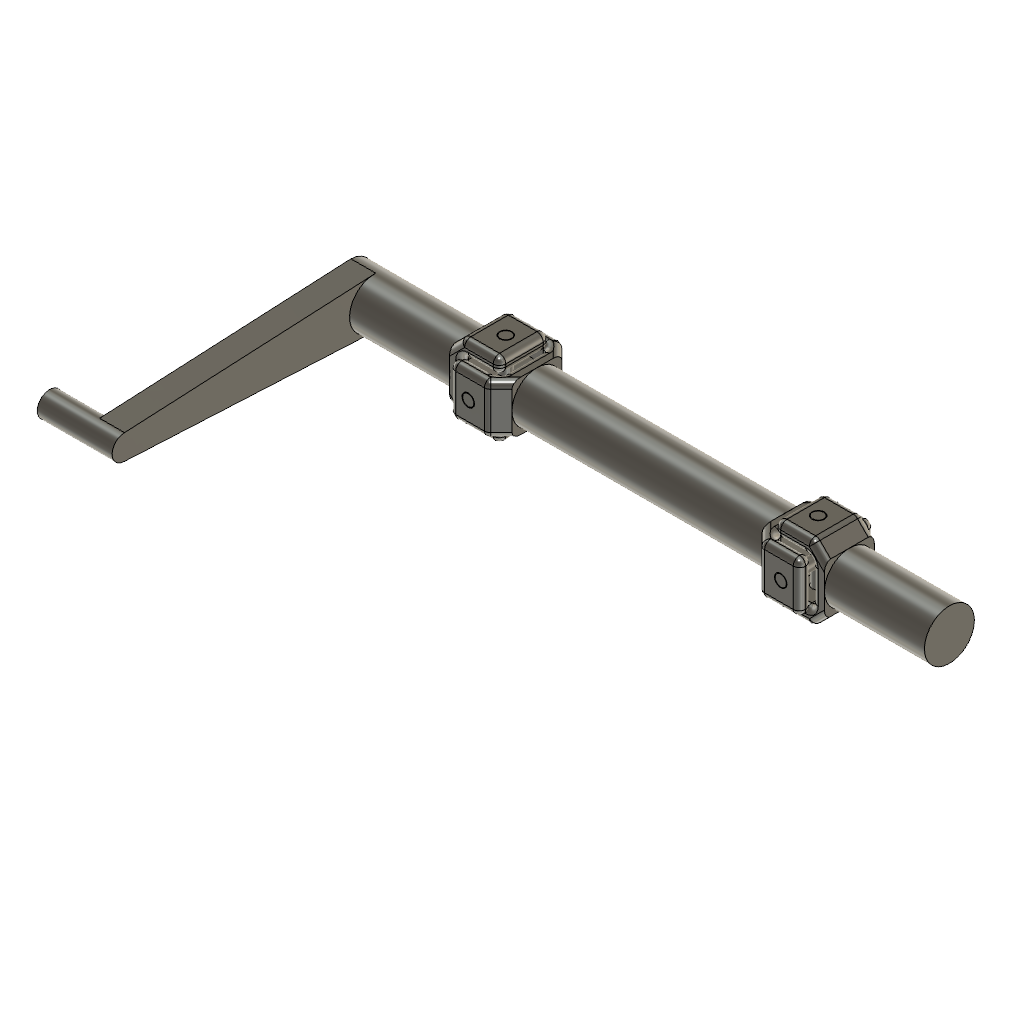
Constant Velocity joint (Autodesk Fusion 360 design; units mm, degrees)
Autodesk Fusion 360 part; units mm, degrees
sketch "Sketch1" plane through (0, 0, 0) normal (1, 0, 0) x (0, 1, 0)
  circle A0 centre (0, 0) radius 1
  dimension "d1" = 2
  constraint coincident A0.centre origin
  measures "d1" diameter of A0
extrude "Extrude1" add sketch "Sketch1" along normal blind 4 makes body 1 in component "Component"
sketch "Sketch2" plane through (0, 0, 0) normal (0, 1, 0) x (1, 0, 0)
  line L0 (4, -1) -> (4.5, -1.5)
  line L1 (4.5, -1.5) -> (6, -1.5)
  line L2 (6, -1.5) -> (6, -0.9)
  line L3 (6, -0.9) -> (4.5, -0.9)
  line L4 (4.5, -0.9) -> (4.5, 0.9)
  line L5 (4.5, 0.9) -> (6, 0.9)
  line L6 (6, 0.9) -> (6, 1.5)
  line L7 (6, 1.5) -> (4.5, 1.5)
  line L8 (4.5, 1.5) -> (4, 1)
  line L9 (4, 1) -> (4, -1)
  constraint horizontal L1
  constraint perpendicular L1 L2
  constraint perpendicular L2 L3
  constraint perpendicular L3 L4
  constraint perpendicular L4 L5
  constraint perpendicular L5 L6
  constraint perpendicular L6 L7
  constraint perpendicular L7 L9
extrude "Extrude2" add sketch "Sketch2" along normal mid plane 2 bodies 1 in component "Component"
fillet "Fillet1" radius 0.25 6 edges at (6, 0, 1.5) (6, 0, 0.9) (4.5, 0, 0.9) (4.5, 0, -0.9) (6, 0, -0.9) (6, 0, -1.5) on bodies 1 in component "Component"
fillet "Fillet1" radius 0.25 2 edges at (4.5, 0, 1.5) (4.5, 0, -1.5) on bodies 1 in component "Component"
sketch "Sketch3" plane through (0, 0, 1.5) normal (0, 0, 1) x (-1, 0, 0)
  line L0 (-4.6036, -1) -> (-4.6036, 1)
  line L1 (-4.6036, 1) -> (-5.75, 1)
  line L2 (-5.75, 1) -> (-5.75, -1)
  line L3 (-5.75, -1) -> (-4.6036, -1)
  circle A0 centre (-5.25, 0) radius 0.25
  dimension "d10" = 0.5
  measures "d10" diameter of A0
extrude "Extrude3" cut sketch "Sketch3" against normal blind 3 contours A0 bodies 1 in component "Component"
sketch "Sketch4" plane through (0, 0, 1.5) normal (0, 0, 1) x (-1, 0, 0)
  circle A0 centre (-5.25, 0) radius 0.25
  line L0 (-4.6036, -1) -> (-4.6036, 1)
  line L1 (-4.6036, 1) -> (-5.75, 1)
  line L2 (-5.75, 1) -> (-5.75, -1)
  line L3 (-5.75, -1) -> (-4.6036, -1)
  circle A1 centre (-5.25, 0) radius 0.2252
  constraint concentric A0 A1
extrude "Extrude1'" add sketch "Sketch4" against normal blind 3 separate body contours A1 makes body 2 in component "Component'"
sketch "Sketch5" plane through (0, 0, 0) normal (0, 1, 0) x (1, 0, 0)
  circle A0 through (5, 1.5, 0) (5.375, 1.5, 0.2165) (5.375, 1.5, -0.2165)
  line L0 (5.25, 1.5) -> (5.25, -1.5)
  circle A1 centre (5.25, 0) radius 0.225
  dimension "d15" = 0.45
  constraint vertical L0
  constraint midpoint L0 A1.centre
  measures "d15" diameter of A1
extrude "Extrude2'" add sketch "Sketch5" along normal mid plane 3 bodies 2 in component "Component'"
sketch "Sketch6" plane through (0, 0, 0) normal (0, 0, 1) x (1, 0, 0)
  line L0 (4.5, 1.5) -> (6, 1.5)
  line L1 (4.5, 1.5) -> (4.5, 1)
  line L2 (4.5, 1) -> (6, 1)
  line L3 (6, 1) -> (6, -1)
  line L4 (6, -1) -> (4.5, -1)
  line L5 (4.5, -1) -> (4.5, -1.5)
  line L6 (4.5, -1.5) -> (6, -1.5)
  line L7 (6, -1.5) -> (6.5, -1)
  line L8 (6.5, -1) -> (6.5, 1)
  line L9 (6.5, 1) -> (6, 1.5)
  constraint horizontal L0
  constraint perpendicular L0 L1
  constraint perpendicular L1 L2
  constraint perpendicular L2 L3
  constraint perpendicular L3 L4
  constraint perpendicular L4 L5
  constraint perpendicular L5 L6
  constraint perpendicular L6 L8
fillet "Fillet2" radius 0.25 34 edges at (4.2134, -1, 1.2134) (4.5079, -1, 1.481) (5.1768, -1, 1.5) (5.9268, -1, 1.4268) (6, -1, 1.2) (5.9268, -1, 0.9732) (5.25, -1, 0.9) (4.5732, -1, 0.8268) (4.5, -1, 0) (4.5732, -1, -0.8268) (5.25, -1, -0.9) (5.9268, -1, -0.9732) (6, -1, -1.2) (5.9268, -1, -1.4268) (5.1768, -1, -1.5) (4.5079, -1, -1.481) (4.2134, -1, -1.2134) (4.2134, 1, -1.2134) (4.5079, 1, -1.481) (5.1768, 1, -1.5) (5.9268, 1, -1.4268) (6, 1, -1.2) (5.9268, 1, -0.9732) (5.25, 1, -0.9) (4.5732, 1, -0.8268) (4.5, 1, 0) (4.5732, 1, 0.8268) (5.25, 1, 0.9) (5.9268, 1, 0.9732) (6, 1, 1.2) (5.9268, 1, 1.4268) (5.1768, 1, 1.5) (4.5079, 1, 1.481) (4.2134, 1, 1.2134) on bodies 1 in component "Component"
extrude "Extrude1''" add sketch "Sketch6" along normal mid plane 2 separate body makes body 3 in component "Component''"
fillet "Fillet1'" radius 0.25 6 edges at (4.5, -1, 0) (4.5, -1.5, 0) (4.5, 1.5, 0) (4.5, 1, 0) (6, -1, 0) (6, 1, 0) on bodies 3 in component "Component''"
fillet "Fillet2'" radius 0.25 2 edges at (6, -1.5, 0) (6, 1.5, 0) on bodies 3 in component "Component''"
fillet "Fillet3" radius 0.25 30 edges at (6.2866, 1.2134, 1) (5.9921, 1.481, 1) (5.3232, 1.5, 1) (4.5732, 1.4268, 1) (4.5732, 1.0732, 1) (5.25, 1, 1) (5.9268, 0.9268, 1) (6, 0, 1) (5.9268, -0.9268, 1) (5.25, -1, 1) (4.5732, -1.0732, 1) (4.5732, -1.4268, 1) (5.3232, -1.5, 1) (5.9921, -1.481, 1) (6.2866, -1.2134, 1) (6.2866, 1.2134, -1) (5.9921, 1.481, -1) (5.3232, 1.5, -1) (4.5732, 1.4268, -1) (4.5732, 1.0732, -1) (5.25, 1, -1) (5.9268, 0.9268, -1) (6, 0, -1) (5.9268, -0.9268, -1) (5.25, -1, -1) (4.5732, -1.0732, -1) (4.5732, -1.4268, -1) (5.3232, -1.5, -1) (5.9921, -1.481, -1) (6.2866, -1.2134, -1) on bodies 3 in component "Component''"
sketch "Sketch7" plane through (0, 1.5, 0) normal (0, 1, 0) x (-1, 0, 0)
  line L0 (-5.8964, -0.75) -> (-4.75, -0.75)
  line L1 (-4.75, -0.75) -> (-4.75, 0.75)
  line L2 (-4.75, 0.75) -> (-5.8964, 0.75)
  line L3 (-5.8964, 0.75) -> (-5.8964, -0.75)
  circle A0 centre (-5.25, 0) radius 0.25
  dimension "d28" = 0.5
  measures "d28" diameter of A0
extrude "Extrude2''" cut sketch "Sketch7" against normal blind 3 contours A0 bodies 3 in component "Component''"
sketch "Sketch8" plane through (6.5, 0, 0) normal (1, 0, 0) x (0, 1, 0)
  ellipse E0 centre (-0.6464, -0.75) end of major axis (-1, -0.75) minor radius 0.25 (-1, -0.75) -> (-0.6464, -1) ccw
  line L0 (-0.6464, -1) -> (0.6464, -1)
  ellipse E1 centre (0.6464, -0.75) end of major axis (1, -0.75) minor radius 0.25 (0.6464, -1) -> (1, -0.75) ccw
  line L1 (1, -0.75) -> (1, 0.75)
  ellipse E2 centre (0.6464, 0.75) end of major axis (1, 0.75) minor radius 0.25 (1, 0.75) -> (0.6464, 1) ccw
  line L2 (0.6464, 1) -> (-0.6464, 1)
  ellipse E3 centre (-0.6464, 0.75) end of major axis (-1, 0.75) minor radius 0.25 (-0.6464, 1) -> (-1, 0.75) ccw
  line L3 (-1, 0.75) -> (-1, -0.75)
  circle A0 centre (0, 0) radius 1
  dimension "d31" = 2
  constraint coincident A0.centre origin
  measures "d31" diameter of A0
extrude "Extrude3'" add sketch "Sketch8" along normal blind 5 contours A0 bodies 3 in component "Component''"
mirror "Mirror1" about plane through (11.5, 0, 0) normal (1, 0, 0) of bodies 3 merged in component "Component''"
sketch "Sketch9" plane through (0, 0, 0) normal (0, 0, 1) x (1, 0, 0)
  line L0 (6.5, 1) -> (16.5, 1)
  line L1 (16.5, 1) -> (16.5, -1)
  line L2 (16.5, -1) -> (6.5, -1)
  line L3 (6.5, -1) -> (6.5, 1)
  line L4 (11.5, 1) -> (11.5, -1)
  constraint horizontal L0
  constraint vertical L1
  constraint horizontal L2
  constraint vertical L3
  constraint midpoint L0 L4.start
  constraint midpoint L2 L4.end
extrude "Extrude1'''" add sketch "Sketch4" against normal blind 3 separate body contours A1 makes body 4 in component "Component'''"
extrude "Extrude2'''" add sketch "Sketch5" along normal mid plane 3 bodies 4 in component "Component'''"
extrude "Extrude1''''" add sketch "Sketch1" along normal blind 4 separate body makes body 5 in component "Component''''"
extrude "Extrude2''''" add sketch "Sketch2" along normal mid plane 2 bodies 5 in component "Component''''"
fillet "Fillet1''" radius 0.25 6 edges at (6, 0, 1.5) (6, 0, 0.9) (4.5, 0, 0.9) (4.5, 0, -0.9) (6, 0, -0.9) (6, 0, -1.5) on bodies 5 in component "Component''''"
fillet "Fillet1''" radius 0.25 2 edges at (4.5, 0, 1.5) (4.5, 0, -1.5) on bodies 5 in component "Component''''"
extrude "Extrude3''" cut sketch "Sketch3" against normal blind 3 contours A0 bodies 5 in component "Component''''"
fillet "Fillet2''" radius 0.25 34 edges at (4.2134, -1, 1.2134) (4.5079, -1, 1.481) (5.1768, -1, 1.5) (5.9268, -1, 1.4268) (6, -1, 1.2) (5.9268, -1, 0.9732) (5.25, -1, 0.9) (4.5732, -1, 0.8268) (4.5, -1, 0) (4.5732, -1, -0.8268) (5.25, -1, -0.9) (5.9268, -1, -0.9732) (6, -1, -1.2) (5.9268, -1, -1.4268) (5.1768, -1, -1.5) (4.5079, -1, -1.481) (4.2134, -1, -1.2134) (4.2134, 1, -1.2134) (4.5079, 1, -1.481) (5.1768, 1, -1.5) (5.9268, 1, -1.4268) (6, 1, -1.2) (5.9268, 1, -0.9732) (5.25, 1, -0.9) (4.5732, 1, -0.8268) (4.5, 1, 0) (4.5732, 1, 0.8268) (5.25, 1, 0.9) (5.9268, 1, 0.9732) (6, 1, 1.2) (5.9268, 1, 1.4268) (5.1768, 1, 1.5) (4.5079, 1, 1.481) (4.2134, 1, 1.2134) on bodies 5 in component "Component''''"
sketch "Sketch10" plane through (0, 0, 0) normal (-1, 0, 0) x (0, -1, 0)
  circle A0 centre (0, 0) radius 1
  line L0 (0, 0) -> (10, 0)
  line L1 (-0.0501, 0.9987) -> (10, 0.5)
  line L2 (10, -0.5) -> (0.0501, -0.9987)
  line L3 (0.0501, -0.9987) -> (-0.0501, 0.9987)
  line L4 (10, 0.5) -> (10, -0.5)
  circle A1 centre (10, 0) radius 0.5
  dimension "d36" = 10
  constraint coincident A0.centre L0.start
  constraint coincident A0 L1.start
  constraint coincident A0 L2.end
  constraint tangent A0 L2
  constraint perpendicular A0 L3
  constraint vertical L4
  constraint coincident L0.end A1.centre
  constraint coincident L2.start A1
  measures "d36" distance of A0.centre L0.end
extrude "Extrude4" add sketch "Sketch10" along normal blind 1 contours A0 L0 L3 | A0 L0 L2 A1 | A0 L0 L3 | A0 L3 | A0 L0 L1 A1 bodies 1 in component "Component"
extrude "Extrude5" add sketch "Sketch10" along normal blind 3 contours L0 L4 A1 | L0 L4 A1 | L4 A1 bodies 1 in component "Component"
component "Component" placed x (1, 0, 0) y (0, 1, 0) z (0, 0, 1) at (0, 0, 0)
component "Component'" placed x (1, 0, 0) y (0, 1, 0) z (0, 0, 1) at (0, 0, 0)
component "Component''" placed x (1, 0, 0) y (0, 1, 0) z (0, 0, 1) at (0, 0, 0)
component "Component'" placed x (1, 0, 0) y (0, 1, 0) z (0, 0, 1) at (0, 0, 0)
component "Component" placed x (1, 0, 0) y (0, 1, 0) z (0, 0, 1) at (0, 0, 0)
component "Component'''" placed x (-1, 0, 0) y (0, -1, 0) z (0, 0, 1) at (22.9999, 0, 0)
component "Component''''" placed x (-1, 0, 0) y (0, -1, 0) z (0, 0, 1) at (22.9999, 0, 0)
